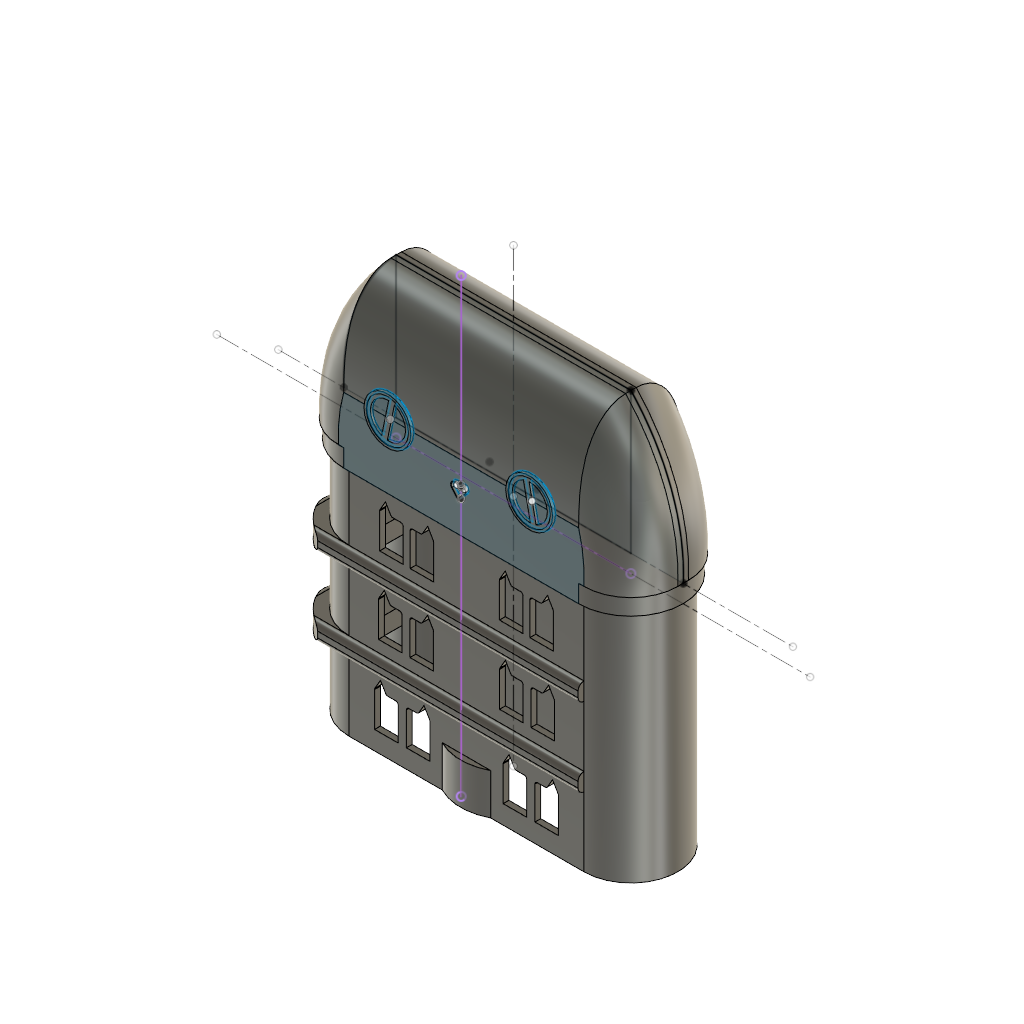
Gabby doll House (Autodesk Fusion 360 design; units mm, degrees)
Autodesk Fusion 360 part; units mm, degrees
sketch "Sketch1" plane through (0, 0, 0) normal (0, 0, 1) x (1, 0, 0)
  line L0 (-100, -40) -> (100, -40)
  arc A0 (100, -40) -> (100, 40) centre (100, 0) ccw
  line L1 (100, 40) -> (-100, 40)
  arc A1 (-100, 40) -> (-100, -40) centre (-100, 0) ccw
  line L2 (-100, 0) -> (100, 0) construction
  dimension "d1" = 100
  dimension "d2" = 40
  constraint tangent L0 A0
  constraint tangent A0 L1
  constraint parallel L0 L1
  constraint tangent L1 A1
  constraint tangent L0 A1
  constraint horizontal L2
  constraint midpoint L2 origin
  measures "d1" distance of A0.centre origin
  measures "d2" radius of A0
extrude "Extrude1" add sketch "Sketch1" along normal blind 200
sketch "Sketch2" plane through (0, 0, 200) normal (0, 0, 1) x (-1, 0, 0)
  arc A0 (100, -40) -> (100, 40) centre (100, 0) ccw
  line L0 (100, 40) -> (-100, 40)
  arc A1 (-100, 40) -> (-100, -40) centre (-100, 0) ccw
  line L1 (-100, -40) -> (100, -40)
  line L2 (95, 35) -> (-95, 35)
  arc A2 (-95, 35) -> (-95, -35) centre (-95, 0) ccw
  line L3 (-95, -35) -> (95, -35)
  arc A3 (95, -35) -> (95, 35) centre (95, 0) ccw
  line L4 (95, 0) -> (-95, 0) construction
  dimension "d5" = 35
  dimension "d6" = 190
  constraint tangent L2 A2
  constraint tangent A2 L3
  constraint parallel L2 L3
  constraint tangent L3 A3
  constraint tangent L2 A3
  constraint parallel L1 L4
  constraint midpoint L4 origin
  measures "d5" radius of A2
  measures "d6" distance of L2.start L2.end
extrude "Extrude2" cut sketch "Sketch2" against normal up to surface (200 mm away) contours L2 A2 L3 A3
sketch "Sketch3" plane through (0, 0, 200) normal (0, 0, 1) x (-1, 0, 0)
  line L0 (95, -35) -> (-95, -35)
  arc A0 (-95, 35) -> (-95, -35) centre (-95, 0) ccw
  line L1 (-95, 35) -> (95, 35)
  arc A1 (95, -35) -> (95, 35) centre (95, 0) ccw
  arc A2 (100, -40) -> (100, 40) centre (100, 0) ccw
  line L2 (100, 40) -> (-100, 40)
  arc A3 (-100, 40) -> (-100, -40) centre (-100, 0) ccw
  line L3 (-100, -40) -> (100, -40)
  line L4 (100, -44.5) -> (-100, -44.5)
  line L5 (100, 44.5) -> (-100, 44.5)
  arc A4 (100, -44.5) -> (100, 44.5) centre (100, 0) ccw
  arc A5 (-100, 44.5) -> (-100, -44.5) centre (-100, 0) ccw
  line L6 (160.5, 0) -> (157.3163, 0)
  line L7 (157.3163, 0) -> (-177.3677, 0)
  dimension "d9" = 89
  dimension "d10" = 200
  dimension "d12" = 200
  dimension "d13" = 44.5
  constraint concentric A2 A4
  constraint tangent L4 A5
  constraint parallel L2 L5
  constraint tangent L4 A4
  constraint tangent L5 A4
  constraint coincident L5 A5.start
  constraint horizontal L6
  constraint parallel L6 L7
  constraint coincident origin L7
  constraint horizontal L4
  measures "d9" diameter of A4
  measures "d10" distance of L4.start L4.end
  measures "d12" distance of L5.start L5.end
  measures "d13" radius of A5
extrude "Extrude3" add sketch "Sketch3" along normal blind 15
ref_plane "WorkPlane1" through (0, 0, 207.5) normal (0, -1, 0) x (1, 0, 0)
sketch "Sketch4" plane through (0, 0, 0) normal (0, -1, 0) x (-1, 0, 0)
  line L0 (252.6221, -200) -> (-252.6221, -200)
  line L1 (0, -200) -> (0, -206.9385)
  line L2 (0, -392.0441) -> (0, -7.9559)
  line L3 (100, -200) -> (-100, -200)
  line L4 (200.2322, -215) -> (-237.9611, -215)
  line L5 (100, -215) -> (-100, -215)
  line L6 (-100, -215) -> (-100, -335)
  line L7 (-100, -335) -> (100, -335)
  line L8 (100, -335) -> (100, -215)
  arc A0 (100, -335) -> (144.5, -215) centre (-20.3463, -222.1205) ccw
  arc A1 (-144.5, -215) -> (-100, -335) centre (20.3463, -222.1205) ccw
  point P0 (144.5, -215)
  dimension "d16" = 15
  dimension "d17" = 200
  dimension "d18" = 120
  dimension "d19" = 100
  dimension "d22" = 44.5
  dimension "d23" = 165
  constraint horizontal L0
  constraint midpoint L0 L1.start
  constraint perpendicular L0 L1
  constraint parallel L1 L2
  constraint midpoint L0 L2
  constraint midpoint L0 L3
  constraint horizontal L5
  constraint vertical L6
  constraint horizontal L7
  constraint vertical L8
  constraint coincident L4 L5.start
  constraint coincident L4 P0
  constraint coincident P0 A0.end
  constraint symmetric L2 L7.end L6.end
  constraint symmetric L2 P0 A1.start
  constraint symmetric L2 A0 A1
  measures "d16" distance of L0 L4
  measures "d17" distance of L6.end L7.end
  measures "d18" distance of L5.end L6.end
  measures "d19" distance of L2 L6
  measures "d22" distance of L5.start P0
  measures "d23" radius of A0
extrude "Extrude4" add sketch "Sketch4" along normal mid plane 90 contours L2 L4 L5 L6 L7 | L2 L4 L5 L7 L8
extrude "Extrude5" add sketch "Sketch4" along normal up to surface (44.5 mm away) and the other way up to surface (44.5 mm away)
fillet "Fillet1" radius 40 1 edges at (134.3589, -44.5, 279.4904)
fillet "Fillet2" radius 40 3 edges at (-134.3589, -44.5, 279.4904) (-134.3589, 44.5, 279.4904) (134.3589, 44.5, 279.4904)
fillet "Fillet3" radius 40 2 edges at (0, -45, 335) (0, 45, 335)
ref_plane "WorkPlane2" through (144.6537, -3.2534, 222.1205) normal (1, 0, 0) x (0, 0, -1)
extrude "Extrude6" cut 2 faces at (100, 40.3874, 304.4074) (100, -39.9876, 305.3457) along direction (1, 0, 0) up to surface end surface through (-100, 0, 335) normal (-1, 0, 0) offset 0
sketch "Sketch7" plane through (0, -40, 0) normal (0, -1, 0) x (1, 0, 0)
  line L0 (-100, 0) -> (100, 0)
  line L1 (100, 0) -> (100, 200)
  line L2 (100, 200) -> (-100, 200)
  line L3 (-100, 200) -> (-100, 0)
  line L4 (0, -23.6441) -> (0, 207.6926)
  line L5 (-175.644, 133.3333) -> (-166.137, 133.3333)
  line L6 (-166.137, 133.3333) -> (177.02, 133.3333)
  line L7 (-167.0425, 66.6667) -> (-160.7045, 66.6667)
  line L8 (-160.7045, 66.6667) -> (182.4525, 66.6667)
  line L9 (-73.9686, 149.7452) -> (-53.9686, 149.7452)
  line L10 (-53.9686, 149.7452) -> (-53.9686, 177.7452)
  line L11 (-55.9686, 179.7452) -> (-62.8182, 179.7452)
  line L12 (-73.9686, 179.2093) -> (-73.9686, 149.7452)
  line L13 (-73.7006, 180.2093) -> (-68.9686, 188.4055)
  line L14 (-68.9686, 188.4055) -> (-64.5507, 180.7459)
  line L15 (-100, 200) -> (-100, -17.3764)
  line L16 (-33.0222, 188.4055) -> (-37.4401, 180.7459)
  line L17 (-28.0222, 149.7452) -> (-48.0222, 149.7452)
  line L18 (-28.2901, 180.2093) -> (-33.0222, 188.4055)
  line L19 (-48.0222, 149.7452) -> (-48.0222, 177.7452)
  line L20 (-46.0222, 179.7452) -> (-39.1726, 179.7452)
  line L21 (-28.0222, 179.2093) -> (-28.0222, 149.7452)
  line L22 (28.0222, 149.7452) -> (48.0222, 149.7452)
  line L23 (28.0222, 179.2093) -> (28.0222, 149.7452)
  line L24 (48.0222, 149.7452) -> (48.0222, 177.7452)
  line L25 (73.7006, 180.2093) -> (68.9686, 188.4055)
  line L26 (46.0222, 179.7452) -> (39.1726, 179.7452)
  line L27 (53.9686, 149.7452) -> (53.9686, 177.7452)
  line L28 (33.0222, 188.4055) -> (37.4401, 180.7459)
  line L29 (73.9686, 149.7452) -> (53.9686, 149.7452)
  line L30 (68.9686, 188.4055) -> (64.5507, 180.7459)
  line L31 (55.9686, 179.7452) -> (62.8182, 179.7452)
  line L32 (73.9686, 179.2093) -> (73.9686, 149.7452)
  line L33 (28.2901, 180.2093) -> (33.0222, 188.4055)
  line L34 (-63.7943, 114.005) -> (-56.949, 114.005)
  line L35 (-54.949, 112.005) -> (-54.949, 84.005)
  line L36 (-54.949, 84.005) -> (-74.949, 84.005)
  line L37 (-74.949, 84.005) -> (-74.949, 113.4691)
  line L38 (-67.1032, 45.9388) -> (-60.2579, 45.9388)
  line L39 (-58.2579, 43.9388) -> (-58.2579, 15.9388)
  line L40 (-58.2579, 15.9388) -> (-78.2579, 15.9388)
  line L41 (-78.2579, 15.9388) -> (-78.2579, 45.4029)
  line L42 (-74.6811, 114.4691) -> (-69.949, 122.6653)
  line L43 (-69.949, 122.6653) -> (-65.5264, 115.005)
  line L44 (-77.9899, 46.4029) -> (-73.2579, 54.599)
  line L45 (-73.2579, 54.599) -> (-68.8352, 46.9388)
  line L46 (-48.1568, 84.005) -> (-28.1568, 84.005)
  line L47 (-48.1568, 112.005) -> (-48.1568, 84.005)
  line L48 (-33.1568, 122.6653) -> (-37.5795, 115.005)
  line L49 (-28.4248, 114.4691) -> (-33.1568, 122.6653)
  line L50 (-28.1568, 84.005) -> (-28.1568, 113.4691)
  line L51 (-39.3115, 114.005) -> (-46.1568, 114.005)
  line L52 (-51.2117, 15.9388) -> (-31.2117, 15.9388)
  line L53 (-42.3664, 45.9388) -> (-49.2117, 45.9388)
  line L54 (-51.2117, 43.9388) -> (-51.2117, 15.9388)
  line L55 (-31.2117, 15.9388) -> (-31.2117, 45.4029)
  line L56 (-31.4797, 46.4029) -> (-36.2117, 54.599)
  line L57 (-36.2117, 54.599) -> (-40.6344, 46.9388)
  line L58 (69.949, 122.6653) -> (65.5264, 115.005)
  line L59 (54.949, 112.005) -> (54.949, 84.005)
  line L60 (51.2117, 15.9388) -> (31.2117, 15.9388)
  line L61 (31.2117, 15.9388) -> (31.2117, 45.4029)
  line L62 (73.2579, 54.599) -> (68.8352, 46.9388)
  line L63 (39.3115, 114.005) -> (46.1568, 114.005)
  line L64 (74.949, 84.005) -> (74.949, 113.4691)
  line L65 (78.2579, 15.9388) -> (78.2579, 45.4029)
  line L66 (58.2579, 43.9388) -> (58.2579, 15.9388)
  line L67 (28.1568, 84.005) -> (28.1568, 113.4691)
  line L68 (33.1568, 122.6653) -> (37.5795, 115.005)
  line L69 (48.1568, 112.005) -> (48.1568, 84.005)
  line L70 (36.2117, 54.599) -> (40.6344, 46.9388)
  line L71 (63.7943, 114.005) -> (56.949, 114.005)
  line L72 (51.2117, 43.9388) -> (51.2117, 15.9388)
  line L73 (42.3664, 45.9388) -> (49.2117, 45.9388)
  line L74 (67.1032, 45.9388) -> (60.2579, 45.9388)
  line L75 (31.4797, 46.4029) -> (36.2117, 54.599)
  line L76 (28.4248, 114.4691) -> (33.1568, 122.6653)
  line L77 (74.6811, 114.4691) -> (69.949, 122.6653)
  line L78 (77.9899, 46.4029) -> (73.2579, 54.599)
  line L79 (48.1568, 84.005) -> (28.1568, 84.005)
  line L80 (54.949, 84.005) -> (74.949, 84.005)
  line L81 (58.2579, 15.9388) -> (78.2579, 15.9388)
  line L82 (-100, 140.8333) -> (100, 140.8333)
  line L83 (100, 140.8333) -> (100, 125.8333)
  line L84 (100, 125.8333) -> (-100, 125.8333)
  line L85 (-100, 125.8333) -> (-100, 140.8333)
  line L86 (-22.4464, 140.8333) -> (-22.0768, 140.8333)
  line L87 (-22.0768, 133.3333) -> (-22.4464, 133.3333)
  line L88 (-100, 74.1667) -> (100, 74.1667)
  line L89 (100, 74.1667) -> (100, 59.1667)
  line L90 (100, 59.1667) -> (-100, 59.1667)
  line L91 (-100, 59.1667) -> (-100, 74.1667)
  arc A0 (-73.6337, 180.3253) -> (-73.9686, 179.0753) centre (-71.4686, 179.0753) ccw
  arc A1 (-64.5507, 180.7459) -> (-62.8182, 179.7452) centre (-62.8182, 181.7452) ccw
  arc A2 (-39.1726, 179.7452) -> (-37.4401, 180.7459) centre (-39.1726, 181.7452) ccw
  arc A3 (-28.0222, 179.2093) -> (-28.2901, 180.2093) centre (-30.0222, 179.2093) ccw
  arc A4 (-73.7006, 180.2093) -> (-73.9686, 179.2093) centre (-71.9686, 179.2093) ccw
  arc A5 (28.2901, 180.2093) -> (28.0222, 179.2093) centre (30.0222, 179.2093) ccw
  arc A6 (37.4401, 180.7459) -> (39.1726, 179.7452) centre (39.1726, 181.7452) ccw
  arc A7 (48.0222, 177.7452) -> (46.0222, 179.7452) centre (46.0222, 177.7452) ccw
  arc A8 (-53.9686, 177.7452) -> (-55.9686, 179.7452) centre (-55.9686, 177.7452) ccw
  arc A9 (-46.0222, 179.7452) -> (-48.0222, 177.7452) centre (-46.0222, 177.7452) ccw
  arc A10 (55.9686, 179.7452) -> (53.9686, 177.7452) centre (55.9686, 177.7452) ccw
  arc A11 (62.8182, 179.7452) -> (64.5507, 180.7459) centre (62.8182, 181.7452) ccw
  arc A12 (73.9686, 179.2093) -> (73.7006, 180.2093) centre (71.9686, 179.2093) ccw
  arc A13 (-74.6811, 114.4691) -> (-74.949, 113.4691) centre (-72.949, 113.4691) ccw
  arc A14 (-65.5264, 115.005) -> (-63.7943, 114.005) centre (-63.7943, 116.005) ccw
  arc A15 (-54.949, 112.005) -> (-56.949, 114.005) centre (-56.949, 112.005) ccw
  arc A16 (-46.1568, 114.005) -> (-48.1568, 112.005) centre (-46.1568, 112.005) ccw
  arc A17 (-39.3115, 114.005) -> (-37.5795, 115.005) centre (-39.3115, 116.005) ccw
  arc A18 (-28.1568, 113.4691) -> (-28.4248, 114.4691) centre (-30.1568, 113.4691) ccw
  arc A19 (28.4248, 114.4691) -> (28.1568, 113.4691) centre (30.1568, 113.4691) ccw
  arc A20 (37.5795, 115.005) -> (39.3115, 114.005) centre (39.3115, 116.005) ccw
  arc A21 (48.1568, 112.005) -> (46.1568, 114.005) centre (46.1568, 112.005) ccw
  arc A22 (56.949, 114.005) -> (54.949, 112.005) centre (56.949, 112.005) ccw
  arc A23 (63.7943, 114.005) -> (65.5264, 115.005) centre (63.7943, 116.005) ccw
  arc A24 (74.949, 113.4691) -> (74.6811, 114.4691) centre (72.949, 113.4691) ccw
  arc A25 (-77.9899, 46.4029) -> (-78.2579, 45.4029) centre (-76.2579, 45.4029) ccw
  arc A26 (-68.8352, 46.9388) -> (-67.1032, 45.9388) centre (-67.1032, 47.9388) ccw
  arc A27 (-58.2579, 43.9388) -> (-60.2579, 45.9388) centre (-60.2579, 43.9388) ccw
  arc A28 (-49.2117, 45.9388) -> (-51.2117, 43.9388) centre (-49.2117, 43.9388) ccw
  arc A29 (-42.3664, 45.9388) -> (-40.6344, 46.9388) centre (-42.3664, 47.9388) ccw
  arc A30 (-31.2117, 45.4029) -> (-31.4797, 46.4029) centre (-33.2117, 45.4029) ccw
  arc A31 (31.4797, 46.4029) -> (31.2117, 45.4029) centre (33.2117, 45.4029) ccw
  arc A32 (40.6344, 46.9388) -> (42.3664, 45.9388) centre (42.3664, 47.9388) ccw
  arc A33 (51.2117, 43.9388) -> (49.2117, 45.9388) centre (49.2117, 43.9388) ccw
  arc A34 (60.2579, 45.9388) -> (58.2579, 43.9388) centre (60.2579, 43.9388) ccw
  arc A35 (67.1032, 45.9388) -> (68.8352, 46.9388) centre (67.1032, 47.9388) ccw
  arc A36 (78.2579, 45.4029) -> (77.9899, 46.4029) centre (76.2579, 45.4029) ccw
  point P0 (-73.9686, 179.7452)
  point P1 (-63.9722, 179.7431)
  point P2 (-74.949, 114.005)
  point P3 (-54.949, 114.005)
  point P4 (-78.2579, 45.9388)
  point P5 (-58.2579, 45.9388)
  point P6 (-64.949, 114.005)
  dimension "d37" = 66.6667
  dimension "d38" = 66.6667
  dimension "d39" = 20
  dimension "d40" = 30
  dimension "d44" = 10
  dimension "d45" = 10
  dimension "d47" = 20
  dimension "d48" = 30
  dimension "d49" = 20
  dimension "d50" = 30
  dimension "d51" = 10
  dimension "d52" = 10
  dimension "d53" = 10
  dimension "d55" = 60
  dimension "d60" = 15
  dimension "d61" = 7.5
  dimension "d62" = 7.5
  dimension "d63" = 15
  dimension "d70" = 2.5
  dimension "d71" = 2
  dimension "d72" = 2
  dimension "d73" = 2
  dimension "d74" = 2
  dimension "d75" = 2
  dimension "d76" = 2
  dimension "d77" = 2
  dimension "d78" = 2
  dimension "d79" = 2
  dimension "d80" = 2
  dimension "d81" = 2
  dimension "d82" = 2
  constraint perpendicular L2 L4
  constraint horizontal L5
  constraint perpendicular L1 L6
  constraint horizontal L7
  constraint parallel L7 L8
  constraint coincident origin L4
  constraint equal L6 L8
  constraint horizontal L9
  constraint vertical L10
  constraint horizontal L11
  constraint vertical L12
  constraint coincident L2.end L3.start
  constraint perpendicular L6 L15
  constraint symmetric L4 L9.start L29.start
  constraint symmetric L4 L9.end L27.start
  constraint symmetric L4 L13.end L25.end
  constraint symmetric L4 L17.end L22.end
  constraint symmetric L4 L16.start L28.start
  constraint symmetric L4 L17.start L22.start
  constraint horizontal L34
  constraint vertical L35
  constraint horizontal L36
  constraint vertical L37
  constraint horizontal L38
  constraint vertical L39
  constraint horizontal L40
  constraint vertical L41
  constraint symmetric L4 L35.end L59.end
  constraint symmetric L4 L36.end L64.start
  constraint symmetric L4 L39.end L66.end
  constraint symmetric L4 L40.end L65.start
  constraint symmetric L4 L42.end L58.start
  constraint symmetric L4 L44.end L62.start
  constraint symmetric L4 L46.end L67.start
  constraint symmetric L4 L48.start L68.start
  constraint symmetric L4 L46.start L69.end
  constraint symmetric L4 L52.end L60.end
  constraint symmetric L4 L52.start L60.start
  constraint symmetric L4 L56.end L70.start
  constraint horizontal L82
  constraint vertical L83
  constraint horizontal L84
  constraint vertical L85
  constraint coincident L1 L83.end
  constraint coincident L15 L82.start
  constraint horizontal L86
  constraint horizontal L87
  constraint coincident L6 L87.start
  constraint coincident L82 L86.start
  constraint horizontal L88
  constraint vertical L89
  constraint horizontal L90
  constraint vertical L91
  constraint coincident L1 L89.end
  constraint coincident L3 L88.start
  constraint coincident P0 L12
  constraint coincident P0 L13
  constraint tangent L12 A0
  constraint tangent L13 A0
  constraint coincident P1 L14
  constraint tangent L14 A1
  constraint tangent L11 A1
  constraint tangent L16 A2
  constraint tangent L20 A2
  constraint tangent L18 A3
  constraint tangent L21 A3
  constraint coincident L12 A0.end
  constraint coincident L13 A0.start
  constraint tangent L12 A4
  constraint tangent L13 A4
  constraint tangent L23 A5
  constraint tangent L33 A5
  constraint tangent L28 A6
  constraint tangent L26 A6
  constraint tangent L26 A7
  constraint tangent L24 A7
  constraint tangent L11 A8
  constraint tangent L10 A8
  constraint tangent L19 A9
  constraint tangent L20 A9
  constraint tangent L27 A10
  constraint tangent L31 A10
  constraint tangent L30 A11
  constraint tangent L31 A11
  constraint equal A10 A11
  constraint tangent L25 A12
  constraint tangent L32 A12
  constraint equal A10 A12
  constraint coincident P2 L37
  constraint coincident P2 L42
  constraint tangent L37 A13
  constraint tangent L42 A13
  constraint coincident P6 L43
  constraint coincident L34 P6
  constraint tangent L43 A14
  constraint tangent L34 A14
  constraint coincident P3 L34
  constraint coincident P3 L35
  constraint tangent L34 A15
  constraint tangent L35 A15
  constraint equal A14 A15
  constraint tangent L47 A16
  constraint tangent L51 A16
  constraint equal A14 A16
  constraint tangent L48 A17
  constraint tangent L51 A17
  constraint equal A14 A17
  constraint tangent L49 A18
  constraint tangent L50 A18
  constraint equal A14 A18
  constraint tangent L67 A19
  constraint tangent L76 A19
  constraint equal A14 A19
  constraint tangent L63 A20
  constraint tangent L68 A20
  constraint equal A14 A20
  constraint tangent L63 A21
  constraint tangent L69 A21
  constraint equal A14 A21
  constraint tangent L59 A22
  constraint tangent L71 A22
  constraint equal A14 A22
  constraint tangent L58 A23
  constraint tangent L71 A23
  constraint equal A14 A23
  constraint tangent L64 A24
  constraint tangent L77 A24
  constraint equal A14 A24
  constraint coincident P4 L41
  constraint coincident P4 L44
  constraint tangent L41 A25
  constraint tangent L44 A25
  constraint equal A14 A25
  constraint tangent L45 A26
  constraint tangent L38 A26
  constraint equal A14 A26
  constraint coincident P5 L38
  constraint coincident P5 L39
  constraint tangent L38 A27
  constraint tangent L39 A27
  constraint equal A14 A27
  constraint tangent L53 A28
  constraint tangent L54 A28
  constraint equal A14 A28
  constraint tangent L53 A29
  constraint tangent L57 A29
  constraint equal A14 A29
  constraint tangent L55 A30
  constraint tangent L56 A30
  constraint equal A14 A30
  constraint tangent L61 A31
  constraint tangent L75 A31
  constraint equal A14 A31
  constraint tangent L70 A32
  constraint tangent L73 A32
  constraint equal A14 A32
  constraint tangent L72 A33
  constraint tangent L73 A33
  constraint equal A14 A33
  constraint tangent L66 A34
  constraint tangent L74 A34
  constraint equal A14 A34
  constraint tangent L62 A35
  constraint tangent L74 A35
  constraint equal A14 A35
  constraint tangent L65 A36
  constraint tangent L78 A36
  constraint equal A14 A36
  measures "d37" distance of L0 L8
  measures "d38" distance of L6 L8
  measures "d39" distance of L9.start L9.end
  measures "d40" distance of L9.start P0
  measures "d44" distance of P0 L13.end
  measures "d45" distance of L13.end P1
  measures "d47" distance of P2 P3
  measures "d48" distance of P2 L36.end
  measures "d49" distance of P4 P5
  measures "d50" distance of P4 L40.end
  measures "d51" distance of P2 L42.end
  measures "d52" distance of L42.end P6
  measures "d53" distance of P4 L44.end
  measures "d55" angle of L34 L42
  measures "d60" distance of L82 L84
  measures "d61" distance of L6 L82
  measures "d62" distance of L8 L88
  measures "d63" distance of L88 L90
  measures "d70" radius of A0
  measures "d71" radius of A1
  measures "d72" radius of A2
  measures "d73" radius of A3
  measures "d74" radius of A4
  measures "d75" radius of A5
  measures "d76" radius of A6
  measures "d77" radius of A7
  measures "d78" radius of A8
  measures "d79" radius of A9
  measures "d80" radius of A10
  measures "d81" radius of A13
  measures "d82" radius of A14
extrude "Extrude7" cut sketch "Sketch7" against normal up to surface (5 mm away) contours L22 L23 L24 L26 L28 L33 A5 A6 A7 | L25 L27 L29 L30 L31 L32 A10 A11 A12 | L34 L35 L36 L37 L42 L43 A13 A14 A15 | L38 L39 L40 L41 L44 L45 A25 A26 A27 | L46 L47 L48 L49 L50 L51 A16 A17 A18 | L52 L53 L54 L55 L56 L57 A28 A29 A30 | L58 L59 L64 L71 L77 L80 A22 A23 A24 | L60 L61 L70 L72 L73 L75 A31 A32 A33 | L62 L65 L66 L74 L78 L81 A34 A35 A36 | L63 L67 L68 L69 L76 L79 A19 A20 A21
extrude "Extrude8" cut sketch "Sketch7" against normal blind 20 contours L9 L10 L11 L12 L13 L14 A0 A1 A8 | L12 L13 A0 A4 | L16 L17 L18 L19 L20 L21 A2 A3 A9
extrude "Extrude9" add sketch "Sketch7" along normal blind 5 contours L3 L4 L8 L15 L90 L91 | L1 L4 L8 L89 L90 | L3 L4 L8 L15 L88 L91 | L1 L4 L8 L88 L89 | L3 L4 L6 L15 L84 L85 L87 | L1 L4 L6 L83 L84 | L3 L4 L6 L15 L82 L85 L86 L87 | L1 L4 L6 L82 L83
fillet "Fillet4" radius 5 1 edges at (0, -45, 140.8333)
fillet "Fillet5" radius 5 3 edges at (0, -45, 125.8333) (0, -45, 74.1667) (0, -45, 59.1667)
sketch "Sketch8" plane through (0, 0, 0) normal (0, 0, 1) x (1, 0, 0)
  line L0 (0, -45) -> (0, 61.6431)
  line L1 (100, -40) -> (100, -45)
  line L2 (100, -45) -> (-100, -45)
  line L3 (-100, -45) -> (-100, -40)
  line L4 (-100, -40) -> (100, -40)
  arc A0 (-20.6155, -40) -> (20.6155, -40) centre (0, 0) ccw
  line L5 (-20.6155, -40) -> (20.6155, -40)
  dimension "d83" = 45
  constraint vertical L0
  constraint coincident L0 A0.centre
  constraint coincident A0.centre origin
  constraint coincident L0.start A0
  constraint coincident L4 A0.start
  constraint coincident L4 A0.end
  measures "d83" radius of A0
extrude "Extrude10" add sketch "Sketch8" along normal blind 35 contours L0 L4 A0 L5 | L0 L4 A0 L5
sketch "Sketch9" plane through (0, -44.5, 0) normal (0, -1, 0) x (1, 0, 0)
  arc A0 (104.4507, 215) -> (100, 255.9107) centre (-20.3463, 222.1205) ccw
  line L0 (100, 255.9107) -> (-100, 255.9107)
  arc A1 (-100, 255.9107) -> (-104.4507, 215) centre (20.3463, 222.1205) ccw
  line L1 (-104.4507, 215) -> (-100, 215)
  line L2 (-100, 215) -> (-100, 200)
  line L3 (-100, 200) -> (100, 200)
  line L4 (100, 200) -> (100, 215)
  line L5 (100, 215) -> (104.4507, 215)
  circle A2 centre (-60.3539, 255.9107) radius 20
  line L6 (0, 392.0441) -> (0, 7.9559)
  circle A3 centre (-60.3539, 255.9107) radius 18
  line L7 (-59.8163, 270.901) -> (-65.7886, 241.9298)
  line L8 (-60.8915, 240.9203) -> (-54.9193, 269.8915)
  arc A4 (-60.8915, 240.9203) -> (-54.9193, 269.8915) centre (-60.3539, 255.9107) ccw
  arc A5 (-59.8163, 270.901) -> (-65.7886, 241.9298) centre (-60.3539, 255.9107) ccw
  circle A6 centre (60.3539, 255.9107) radius 18
  arc A7 (54.9193, 269.8915) -> (60.8915, 240.9203) centre (60.3539, 255.9107) ccw
  line L9 (60.8915, 240.9203) -> (54.9193, 269.8915)
  line L10 (59.8163, 270.901) -> (65.7886, 241.9298)
  circle A8 centre (60.3539, 255.9107) radius 20
  arc A9 (65.7886, 241.9298) -> (59.8163, 270.901) centre (60.3539, 255.9107) ccw
  line L11 (-5.3016, 234.3913) -> (0, 228.05)
  arc A10 (0, 236.3155) -> (-5.3016, 234.3913) centre (-3, 236.3155) ccw
  line L12 (-5.6858, 234.0713) -> (0, 227.267)
  arc A11 (0, 238.1183) -> (-5.6858, 234.0713) centre (-3, 236.3155) ccw
  arc A12 (5.6858, 234.0713) -> (0, 238.1183) centre (3, 236.3155) ccw
  arc A13 (5.3016, 234.3913) -> (0, 236.3155) centre (3, 236.3155) ccw
  line L13 (5.3016, 234.3913) -> (0, 228.05)
  line L14 (5.6858, 234.0713) -> (0, 227.267)
  dimension "d86" = 40
  dimension "d87" = 36
  dimension "d88" = 30
  dimension "d90" = 2.5
  dimension "d92" = 28.9712
  dimension "d93" = 2.5
  dimension "d98" = 3
  dimension "d99" = 7
  constraint coincident L0 A2.centre
  constraint concentric A2 A3
  constraint concentric A2 A4
  constraint coincident L7.start A4
  constraint parallel L7 L8
  constraint concentric A4 A5
  constraint symmetric A2 L6 A8
  constraint symmetric L6 A3 A6
  constraint symmetric L6 L7.start L10.start
  constraint symmetric L6 L7.end L10.end
  constraint symmetric L6 L8.start A7.end
  constraint symmetric L6 L8.end A7.start
  constraint symmetric L6 A4 A7
  constraint symmetric L6 A5 A9
  constraint tangent L6 A10
  constraint coincident L6 L11.end
  constraint tangent L11 A10
  constraint coincident L6 A10.start
  constraint concentric A10 A11
  constraint coincident L6 L12.end
  constraint tangent L12 A11
  constraint coincident L6 A11.start
  constraint symmetric L6 L11.start A13.start
  constraint symmetric L6 L11.end L13.end
  constraint symmetric L6 A10.start A13.end
  constraint symmetric L6 A10 A13
  constraint symmetric L6 L12.start A12.start
  constraint symmetric L6 L12.end L14.end
  constraint symmetric L6 A11 A12
  constraint symmetric L6 A11.start A12.end
  measures "d86" diameter of A2
  measures "d87" diameter of A3
  measures "d88" diameter of A4
  measures "d90" distance of A2.centre L7
  measures "d92" vertical distance of L7.start L7.end
  measures "d93" distance of A2.centre L8
  measures "d98" distance of L6 A10.centre
  measures "d99" diameter of A11
extrude "Extrude11" add sketch "Sketch9" along normal blind 2.5 contours L0 A6 A8 | L0 A6 A8 | L0 A2 A3 | L0 A2 A3
extrude "Extrude12" add sketch "Sketch9" along normal blind 2 contours L0 A6 A7 L9 L10 A9 | L0 A6 A7 L9 L10 A9 | L0 A3 L7 L8 A4 A5 | L0 A3 L7 L8 A4 A5
extrude "Extrude13" add sketch "Sketch9" along normal blind 2.5 contours L6 L11 A10 L12 A11 | L6 A12 A13 L13 L14
ref_plane "WorkPlane5" through (-175, 0, 0) normal (1, 0, 0) x (0, 1, 0)
sketch "Sketch13" plane through (-175, 0, 0) normal (1, 0, 0) x (0, 1, 0)
  arc A0 (-45, 64.1667) -> (-40, 59.1667) centre (-40, 64.1667) ccw
  line L0 (-45, 64.1667) -> (-45, 69.1667)
  arc A1 (-40, 74.1667) -> (-45, 69.1667) centre (-40, 69.1667) ccw
  line L1 (-40, 74.1667) -> (-40, 59.1667)
  line L2 (40, 0) -> (-40, 0)
  line L3 (-40, 0) -> (-40, 59.1667)
  line L4 (-40, 59.1667) -> (-40, 74.1667)
  line L5 (-40, 74.1667) -> (-40, 125.8333)
  line L6 (-40, 125.8333) -> (-40, 140.8333)
  line L7 (-40, 140.8333) -> (-40, 200)
  line L8 (40, 200) -> (-40, 200)
  line L9 (40, 200) -> (40, 0)
  arc A2 (-45, 130.8333) -> (-40, 125.8333) centre (-40, 130.8333) ccw
  line L10 (-45, 130.8333) -> (-45, 135.8333)
  arc A3 (-40, 140.8333) -> (-45, 135.8333) centre (-40, 135.8333) ccw
  line L11 (-40, 140.8333) -> (-40, 125.8333)
  line L12 (-45, 59.1667) -> (40, 59.1667)
  line L13 (40, 59.1667) -> (40, 74.1667)
  line L14 (40, 74.1667) -> (-45, 74.1667)
  line L15 (-45, 74.1667) -> (-45, 59.1667)
  line L16 (-45, 140.8333) -> (40, 140.8333)
  line L17 (40, 140.8333) -> (40, 125.8333)
  line L18 (40, 125.8333) -> (-45, 125.8333)
  line L19 (-45, 125.8333) -> (-45, 140.8333)
  dimension "d123" = 15
  constraint horizontal L12
  constraint vertical L13
  constraint horizontal L14
  constraint vertical L15
  constraint coincident L9 L13.end
  constraint horizontal L16
  constraint vertical L17
  constraint horizontal L18
  constraint vertical L19
  constraint coincident L9 L17.end
  constraint coincident A2.start L19
  constraint coincident A0.start L15
  constraint coincident A1.start L14
  measures "d123" distance of L12 L14
extrude "Extrude17" add sketch "Sketch13" along normal up to surface (75 mm away) contours A0 L0 A1 L1 L4 L15 | A0 L12 L15 | L1 L4 L9 L12 L13 L14 | A1 L14 L15 | L6 A2 L10 A3 L11 L19 | A2 L18 L19 | L6 L9 L11 L16 L17 L18 | A3 L16 L19
fillet "Fillet7" radius 5 8 edges at (-137.5, -45, 140.8333) (-137.5, -45, 125.8333) (-137.5, -45, 74.1667) (-137.5, -45, 59.1667) (-137.5, 40, 140.8333) (-137.5, 40, 125.8333) (-137.5, 40, 74.1667) (-137.5, 40, 59.1667)
move_face "MoveFace2" by (25, 0, 0) 2 faces at (-175, 10, 130.8333) (-175, 10, 64.1667)
fillet "Fillet8" radius 7 16 edges at (-150, 38.5355, 139.3689) (-150, 40, 133.3333) (-150, 38.5355, 127.2978) (-150, -2.5, 125.8333) (-150, -43.5355, 127.2978) (-150, -45, 133.3333) (-150, -43.5355, 139.3689) (-150, -2.5, 140.8333) (-150, -45, 66.6667) (-150, -43.5355, 60.6311) (-150, -2.5, 59.1667) (-150, 38.5355, 60.6311) (-150, 40, 66.6667) (-150, 38.5355, 72.7022) (-150, -2.5, 74.1667) (-150, -43.5355, 72.7022)
sketch "Sketch14" plane through (0, 0, 140.8333) normal (0, 0, 1) x (-1, 0, 0)
  line L0 (143, -35) -> (143, 40)
  line L1 (143, 40) -> (100, 40)
  arc A0 (119.3649, -35) -> (100, 40) centre (100, 0) ccw
  line L2 (119.3649, -35) -> (143, -35)
  arc A1 (121.5, -45.1345) -> (121.5, 45.1345) centre (100, 0) ccw
  arc A2 (121.5, -63.6696) -> (121.5, 63.6696) centre (100, 0) ccw
  line L3 (121.5, 45.1345) -> (121.5, 63.6696)
  line L4 (121.5, -63.6696) -> (121.5, -45.1345)
  line L5 (121.5, -35) -> (121.5, -33.7305)
  constraint concentric A0 A1
  constraint concentric A1 A2
  constraint perpendicular L1 L4
  constraint coincident A0 L5.end
  constraint collinear L3 L4
  constraint coincident L2 L5.start
  constraint collinear L4 L5
extrude "Extrude18" cut sketch "Sketch14" along normal mid plane 500 contours L0 L2 A1 | L0 L1 L2 A1 A2 L3 L4 | L0 L1 A1
extrude "Extrude16" [suppressed]
delete_face "DeleteFace1" [suppressed]
delete_face "DeleteFace2" [suppressed]
moveface "MoveFace1" [suppressed]
fillet "Fillet6" [suppressed]
extrude "Extrude14" [suppressed]
extrude "Extrude15" [suppressed]
equation "d13 = ( 89 / 2 ) * 1 mm"
equation "d37 = ( 200 / 3 ) * 1 mm"
equation "d38 = ( 200 / 3 ) * 1 mm"
